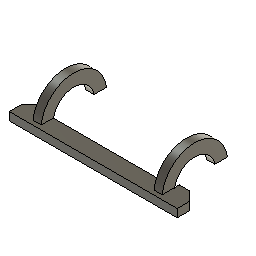
Internal_Pipe_Holders (Autodesk Fusion 360 design; units mm, degrees)
part number: 2025-12-02-10-36-15-577
Autodesk Fusion 360 part; units mm, degrees
sketch "Sketch1" plane through (0, 0, 0) normal (0, 0, 1) x (1, 0, 0)
  line L0 (0, 10.16) -> (80, 10.16)
  line L1 (80, 10.16) -> (80, 0) construction
  line L2 (80, 0) -> (0, 0)
  line L3 (0, 0) -> (0, 10.16) construction
  line L4 (80, 0) -> (92, 0)
  line L5 (92, 0) -> (92, 7.6781)
  line L6 (92, 7.6781) -> (86.3431, 13.335)
  line L7 (86.3431, 13.335) -> (80, 13.335)
  line L8 (80, 13.335) -> (80, 10.16)
  line L9 (40, 0) -> (40, 10.16) construction
  line L10 (80, 0) -> (80, 10.16) construction
  line L11 (-12, 0) -> (-12, 7.6781)
  line L12 (-12, 7.6781) -> (-6.3431, 13.335)
  line L13 (-6.3431, 13.335) -> (0, 13.335)
  line L14 (0, 13.335) -> (0, 10.16)
  line L15 (0, 0) -> (-12, 0)
  dimension "d1" = 80
  dimension "d2" = 10.16
  dimension "d5" = 3.175
  dimension "d6" = 12
  dimension "d7" = 8
  dimension "d8" = 135
  constraint horizontal L0
  constraint vertical L1
  constraint horizontal L2
  constraint vertical L3
  constraint coincident L2.end L3.start
  constraint perpendicular L1 L4
  constraint perpendicular L2 L5
  constraint perpendicular L5 L7
  constraint coincident L0 L1.start
  constraint perpendicular L0 L8
  constraint coincident L0.end L1.start
  constraint midpoint L2 L9.start
  constraint midpoint L0 L9.end
  constraint symmetric L0.start L9 L0.end
  constraint symmetric L1.end L9 L2.end
  constraint symmetric L2.end L9 L1.end
  constraint symmetric L4.end L9 L11.start
  constraint symmetric L5.end L9 L11.end
  constraint symmetric L6.end L9 L12.end
  constraint symmetric L7.end L9 L13.end
  constraint symmetric L0.end L9 L0.start
  measures "d1" distance of L1.end L2.end
  measures "d2" distance of L0 L2
  measures "d5" distance of L0 L7
  measures "d6" distance of L1.end L4.end
  measures "d7" distance of L5.end L6.end
  measures "d8" angle of L6 L7
extrude "Extrude1" add sketch "Sketch1" along normal blind 5 makes body 1
sketch "Sketch4" plane through (0, 0, 0) normal (1, 0, 0) x (0, 1, 0)
  circle A0 centre (22.8791, 2.5019) radius 12.7191
  circle A1 centre (22.8791, 2.5019) radius 20.32
  line L0 (2.7137, 5.0038) -> (43.0444, 5.0038)
  dimension "d11" = 25.4381
  dimension "d12" = 22.8791
  dimension "d13" = 2.5019
  dimension "d14" = 40.64
  dimension "d15" = 5.0038
  constraint concentric A0 A1
  constraint coincident A1 L0.start
  constraint coincident A1 L0.end
  constraint horizontal L0
  measures "d11" diameter of A0
  measures "d12" horizontal distance of origin A0.centre
  measures "d13" vertical distance of origin A0.centre
  measures "d14" diameter of A1
  measures "d15" distance of origin L0
extrude "Extrude2" add sketch "Sketch4" along normal blind 5.08 separate body contours A0 A1 L0 picked at (21.5961, 20.2064) makes body 2
extrude "Extrude3" add 1 faces at (5.08, 21.5961, 20.2064) along direction (-1, 0, 0) blind 5.08 from surface at -74.92 on bodies 2 bodies 2 makes body 3
sketch "Sketch2" plane through (0, 0, 0) normal (0, 0, 1) x (1, 0, 0)
  line L0 (6.9524, 19.8078) -> (-3.0171, 19.8078)
  line L1 (-3.0171, 19.8078) -> (-3.0171, 44.9938)
  line L2 (-3.0171, 44.9938) -> (6.9524, 44.9938)
  line L3 (6.9524, 44.9938) -> (6.9524, 19.8078)
  constraint horizontal L0
  constraint vertical L1
  constraint horizontal L2
  constraint vertical L3
sketch "Sketch3" plane through (0, 0, 0) normal (0, 0, 1) x (1, 0, 0)
  line L0 (86.8286, 19.342) -> (99.5286, 19.342)
  line L1 (99.5286, 19.342) -> (99.5286, 32.042)
  line L2 (99.5286, 32.042) -> (86.8286, 32.042)
  line L3 (86.8286, 32.042) -> (86.8286, 19.342)
  line L4 (86.8286, 29.502) -> (86.8286, 19.342)
  line L5 (86.8286, 19.342) -> (6.8286, 19.342)
  dimension "d3" = 12.7
  dimension "d4" = 12.7
  constraint horizontal L0
  constraint vertical L1
  constraint horizontal L2
  constraint vertical L3
  constraint collinear L3 L4
  constraint collinear L0 L5
  measures "d3" distance of L0.end L1.end
  measures "d4" distance of L1.end L2.end
